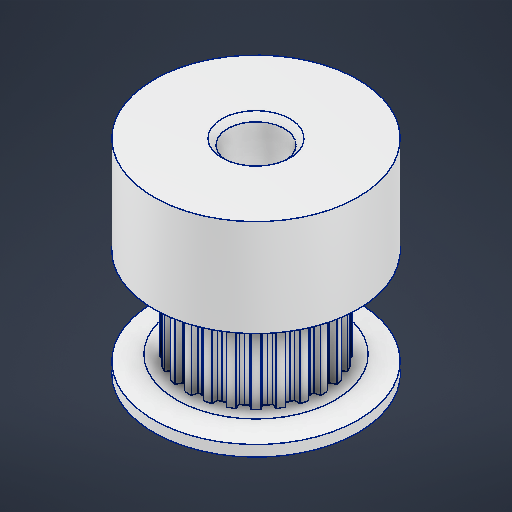
# Autodesk Inventor part: 24 Timing Belt Pulli
Saved by Autodesk Inventor 2026.2 (Build 302298010, 298A)
## iProperties
Created: 2026-04-26
Part Number: 24 Timing Belt Pulli
Material: 알루미늄 6061
Document SubType Name: Modeling
Designer: work
Density: 2.7 g/cm^3
Appearance: 알루미늄 - 평지
Author: work
Autodesk Inventor part; units mm, degrees
ref_plane "YZ Plane" through (0, 0, 0) normal (1, 0, 0) x (0, 1, 0)
ref_plane "XZ Plane" through (0, 0, 0) normal (0, 1, 0) x (-1, 0, 0)
ref_plane "XY Plane" through (0, 0, 0) normal (0, 0, 1) x (1, 0, 0)
sketch "스케치1" plane through (0, 0, 0) normal (0, 1, 0) x (-1, 0, 0)
  circle A0 centre (0, 0) radius 9
  circle A1 centre (0, 0) radius 2.5
  dimension "d0" = 18
  dimension "d1" = 5
  constraints: 2 centre point, 2 coincident
  measures "d0" diameter of A0
  measures "d1" diameter of A1
extrude "돌출1" add sketch "스케치1" along normal blind 18
ref_plane "작업 평면1" through (0, 1.5, 0) normal (0, -1, 0) x (1, 0, 0)
sketch "스케치2" plane through (0, 1.5, 0) normal (0, -1, 0) x (1, 0, 0)
  circle A0 centre (0, 0) radius 9 projected
  circle A1 centre (0, 0) radius 2.5 projected
  line L0 (0, 0) -> (0, -6) construction
  line L1 (0, -6) -> (0.3045, -6)
  line L2 (0.3045, -6) -> (0.3927, -5.5)
  line L3 (0.3927, -5.5) -> (0.7854, -5.5)
  line L4 (0, -6) -> (-0.3045, -6)
  line L5 (-0.3045, -6) -> (-0.3927, -5.5)
  line L6 (-0.3927, -5.5) -> (-0.7854, -5.5)
  line L7 (0, 0) -> (1.5529, -5.7956) construction
  line L8 (1.5529, -5.7956) -> (1.8471, -5.7167)
  line L9 (1.8471, -5.7167) -> (1.8028, -5.211)
  line L10 (1.8028, -5.211) -> (2.1821, -5.1093)
  line L11 (1.5529, -5.7956) -> (1.2588, -5.8744)
  line L12 (1.2588, -5.8744) -> (1.0442, -5.4142)
  line L13 (1.0442, -5.4142) -> (0.6649, -5.5159)
  line L14 (0, 0) -> (3, -5.1962) construction
  line L15 (3, -5.1962) -> (3.2637, -5.0439)
  line L16 (3.2637, -5.0439) -> (3.0901, -4.5668)
  line L17 (3.0901, -4.5668) -> (3.4302, -4.3704)
  line L18 (3, -5.1962) -> (2.7363, -5.3484)
  line L19 (2.7363, -5.3484) -> (2.4099, -4.9595)
  line L20 (2.4099, -4.9595) -> (2.0698, -5.1558)
  line L21 (0, 0) -> (4.2426, -4.2426) construction
  line L22 (4.2426, -4.2426) -> (4.458, -4.0273)
  line L23 (4.458, -4.0273) -> (4.1668, -3.6114)
  line L24 (4.1668, -3.6114) -> (4.4444, -3.3337)
  line L25 (4.2426, -4.2426) -> (4.0273, -4.458)
  line L26 (4.0273, -4.458) -> (3.6114, -4.1668)
  line L27 (3.6114, -4.1668) -> (3.3337, -4.4444)
  line L28 (0, 0) -> (5.1962, -3) construction
  line L29 (5.1962, -3) -> (5.3484, -2.7363)
  line L30 (5.3484, -2.7363) -> (4.9595, -2.4099)
  line L31 (4.9595, -2.4099) -> (5.1558, -2.0698)
  line L32 (5.1962, -3) -> (5.0439, -3.2637)
  line L33 (5.0439, -3.2637) -> (4.5668, -3.0901)
  line L34 (4.5668, -3.0901) -> (4.3704, -3.4302)
  line L35 (0, 0) -> (5.7956, -1.5529) construction
  line L36 (5.7956, -1.5529) -> (5.8744, -1.2588)
  line L37 (5.8744, -1.2588) -> (5.4142, -1.0442)
  line L38 (5.4142, -1.0442) -> (5.5159, -0.6649)
  line L39 (5.7956, -1.5529) -> (5.7167, -1.8471)
  line L40 (5.7167, -1.8471) -> (5.211, -1.8028)
  line L41 (5.211, -1.8028) -> (5.1093, -2.1821)
  line L42 (0, 0) -> (6, 0) construction
  line L43 (6, 0) -> (6, 0.3045)
  line L44 (6, 0.3045) -> (5.5, 0.3927)
  line L45 (5.5, 0.3927) -> (5.5, 0.7854)
  line L46 (6, 0) -> (6, -0.3045)
  line L47 (6, -0.3045) -> (5.5, -0.3927)
  line L48 (5.5, -0.3927) -> (5.5, -0.7854)
  line L49 (0, 0) -> (5.7956, 1.5529) construction
  line L50 (5.7956, 1.5529) -> (5.7167, 1.8471)
  line L51 (5.7167, 1.8471) -> (5.211, 1.8028)
  line L52 (5.211, 1.8028) -> (5.1093, 2.1821)
  line L53 (5.7956, 1.5529) -> (5.8744, 1.2588)
  line L54 (5.8744, 1.2588) -> (5.4142, 1.0442)
  line L55 (5.4142, 1.0442) -> (5.5159, 0.6649)
  line L56 (0, 0) -> (5.1962, 3) construction
  line L57 (5.1962, 3) -> (5.0439, 3.2637)
  line L58 (5.0439, 3.2637) -> (4.5668, 3.0901)
  line L59 (4.5668, 3.0901) -> (4.3704, 3.4302)
  line L60 (5.1962, 3) -> (5.3484, 2.7363)
  line L61 (5.3484, 2.7363) -> (4.9595, 2.4099)
  line L62 (4.9595, 2.4099) -> (5.1558, 2.0698)
  line L63 (0, 0) -> (4.2426, 4.2426) construction
  line L64 (4.2426, 4.2426) -> (4.0273, 4.458)
  line L65 (4.0273, 4.458) -> (3.6114, 4.1668)
  line L66 (3.6114, 4.1668) -> (3.3337, 4.4444)
  line L67 (4.2426, 4.2426) -> (4.458, 4.0273)
  line L68 (4.458, 4.0273) -> (4.1668, 3.6114)
  line L69 (4.1668, 3.6114) -> (4.4444, 3.3337)
  line L70 (0, 0) -> (3, 5.1962) construction
  line L71 (3, 5.1962) -> (2.7363, 5.3484)
  line L72 (2.7363, 5.3484) -> (2.4099, 4.9595)
  line L73 (2.4099, 4.9595) -> (2.0698, 5.1558)
  line L74 (3, 5.1962) -> (3.2637, 5.0439)
  line L75 (3.2637, 5.0439) -> (3.0901, 4.5668)
  line L76 (3.0901, 4.5668) -> (3.4302, 4.3704)
  line L77 (0, 0) -> (1.5529, 5.7956) construction
  line L78 (1.5529, 5.7956) -> (1.2588, 5.8744)
  line L79 (1.2588, 5.8744) -> (1.0442, 5.4142)
  line L80 (1.0442, 5.4142) -> (0.6649, 5.5159)
  line L81 (1.5529, 5.7956) -> (1.8471, 5.7167)
  line L82 (1.8471, 5.7167) -> (1.8028, 5.211)
  line L83 (1.8028, 5.211) -> (2.1821, 5.1093)
  line L84 (0, 0) -> (0, 6) construction
  line L85 (0, 6) -> (-0.3045, 6)
  line L86 (-0.3045, 6) -> (-0.3927, 5.5)
  line L87 (-0.3927, 5.5) -> (-0.7854, 5.5)
  line L88 (0, 6) -> (0.3045, 6)
  line L89 (0.3045, 6) -> (0.3927, 5.5)
  line L90 (0.3927, 5.5) -> (0.7854, 5.5)
  line L91 (0, 0) -> (-1.5529, 5.7956) construction
  line L92 (-1.5529, 5.7956) -> (-1.8471, 5.7167)
  line L93 (-1.8471, 5.7167) -> (-1.8028, 5.211)
  line L94 (-1.8028, 5.211) -> (-2.1821, 5.1093)
  line L95 (-1.5529, 5.7956) -> (-1.2588, 5.8744)
  line L96 (-1.2588, 5.8744) -> (-1.0442, 5.4142)
  line L97 (-1.0442, 5.4142) -> (-0.6649, 5.5159)
  line L98 (0, 0) -> (-3, 5.1962) construction
  line L99 (-3, 5.1962) -> (-3.2637, 5.0439)
  line L100 (-3.2637, 5.0439) -> (-3.0901, 4.5668)
  line L101 (-3.0901, 4.5668) -> (-3.4302, 4.3704)
  line L102 (-3, 5.1962) -> (-2.7363, 5.3484)
  line L103 (-2.7363, 5.3484) -> (-2.4099, 4.9595)
  line L104 (-2.4099, 4.9595) -> (-2.0698, 5.1558)
  line L105 (0, 0) -> (-4.2426, 4.2426) construction
  line L106 (-4.2426, 4.2426) -> (-4.458, 4.0273)
  line L107 (-4.458, 4.0273) -> (-4.1668, 3.6114)
  line L108 (-4.1668, 3.6114) -> (-4.4444, 3.3337)
  line L109 (-4.2426, 4.2426) -> (-4.0273, 4.458)
  line L110 (-4.0273, 4.458) -> (-3.6114, 4.1668)
  line L111 (-3.6114, 4.1668) -> (-3.3337, 4.4444)
  line L112 (0, 0) -> (-5.1962, 3) construction
  line L113 (-5.1962, 3) -> (-5.3484, 2.7363)
  line L114 (-5.3484, 2.7363) -> (-4.9595, 2.4099)
  line L115 (-4.9595, 2.4099) -> (-5.1558, 2.0698)
  line L116 (-5.1962, 3) -> (-5.0439, 3.2637)
  line L117 (-5.0439, 3.2637) -> (-4.5668, 3.0901)
  line L118 (-4.5668, 3.0901) -> (-4.3704, 3.4302)
  line L119 (0, 0) -> (-5.7956, 1.5529) construction
  line L120 (-5.7956, 1.5529) -> (-5.8744, 1.2588)
  line L121 (-5.8744, 1.2588) -> (-5.4142, 1.0442)
  line L122 (-5.4142, 1.0442) -> (-5.5159, 0.6649)
  line L123 (-5.7956, 1.5529) -> (-5.7167, 1.8471)
  line L124 (-5.7167, 1.8471) -> (-5.211, 1.8028)
  line L125 (-5.211, 1.8028) -> (-5.1093, 2.1821)
  line L126 (0, 0) -> (-6, 0) construction
  line L127 (-6, 0) -> (-6, -0.3045)
  line L128 (-6, -0.3045) -> (-5.5, -0.3927)
  line L129 (-5.5, -0.3927) -> (-5.5, -0.7854)
  line L130 (-6, 0) -> (-6, 0.3045)
  line L131 (-6, 0.3045) -> (-5.5, 0.3927)
  line L132 (-5.5, 0.3927) -> (-5.5, 0.7854)
  line L133 (0, 0) -> (-5.7956, -1.5529) construction
  line L134 (-5.7956, -1.5529) -> (-5.7167, -1.8471)
  line L135 (-5.7167, -1.8471) -> (-5.211, -1.8028)
  line L136 (-5.211, -1.8028) -> (-5.1093, -2.1821)
  line L137 (-5.7956, -1.5529) -> (-5.8744, -1.2588)
  line L138 (-5.8744, -1.2588) -> (-5.4142, -1.0442)
  line L139 (-5.4142, -1.0442) -> (-5.5159, -0.6649)
  line L140 (0, 0) -> (-5.1962, -3) construction
  line L141 (-5.1962, -3) -> (-5.0439, -3.2637)
  line L142 (-5.0439, -3.2637) -> (-4.5668, -3.0901)
  line L143 (-4.5668, -3.0901) -> (-4.3704, -3.4302)
  line L144 (-5.1962, -3) -> (-5.3484, -2.7363)
  line L145 (-5.3484, -2.7363) -> (-4.9595, -2.4099)
  line L146 (-4.9595, -2.4099) -> (-5.1558, -2.0698)
  line L147 (0, 0) -> (-4.2426, -4.2426) construction
  line L148 (-4.2426, -4.2426) -> (-4.0273, -4.458)
  line L149 (-4.0273, -4.458) -> (-3.6114, -4.1668)
  line L150 (-3.6114, -4.1668) -> (-3.3337, -4.4444)
  line L151 (-4.2426, -4.2426) -> (-4.458, -4.0273)
  line L152 (-4.458, -4.0273) -> (-4.1668, -3.6114)
  line L153 (-4.1668, -3.6114) -> (-4.4444, -3.3337)
  line L154 (0, 0) -> (-3, -5.1962) construction
  line L155 (-3, -5.1962) -> (-2.7363, -5.3484)
  line L156 (-2.7363, -5.3484) -> (-2.4099, -4.9595)
  line L157 (-2.4099, -4.9595) -> (-2.0698, -5.1558)
  line L158 (-3, -5.1962) -> (-3.2637, -5.0439)
  line L159 (-3.2637, -5.0439) -> (-3.0901, -4.5668)
  line L160 (-3.0901, -4.5668) -> (-3.4302, -4.3704)
  line L161 (0, 0) -> (-1.5529, -5.7956) construction
  line L162 (-1.5529, -5.7956) -> (-1.2588, -5.8744)
  line L163 (-1.2588, -5.8744) -> (-1.0442, -5.4142)
  line L164 (-1.0442, -5.4142) -> (-0.6649, -5.5159)
  line L165 (-1.5529, -5.7956) -> (-1.8471, -5.7167)
  line L166 (-1.8471, -5.7167) -> (-1.8028, -5.211)
  line L167 (-1.8028, -5.211) -> (-2.1821, -5.1093)
  point P0 (-0.7241, -5.5)
  point P1 (-2.1229, -5.1252)
  point P2 (-3.3771, -4.4011)
  point P3 (-4.4011, -3.3771)
  point P4 (-5.1252, -2.1229)
  point P5 (-5.5, -0.7241)
  point P6 (-5.5, 0.7241)
  point P7 (-5.1252, 2.1229)
  point P8 (-4.4011, 3.3771)
  point P9 (-3.3771, 4.4011)
  point P10 (-2.1229, 5.1252)
  point P11 (-0.7241, 5.5)
  point P12 (0.7241, 5.5)
  point P13 (2.1229, 5.1252)
  point P14 (3.3771, 4.4011)
  point P15 (4.4011, 3.3771)
  point P16 (5.1252, 2.1229)
  point P17 (5.5, 0.7241)
  point P18 (5.5, -0.7241)
  point P19 (5.1252, -2.1229)
  point P20 (4.4011, -3.3771)
  point P21 (3.3771, -4.4011)
  point P22 (2.1229, -5.1252)
  point P23 (0.7241, -5.5)
  dimension "d5" = 1.5708
  dimension "d6" = 6
  dimension "d7" = 100
  dimension "d8" = 0.3927
  dimension "d9" = 0.5
  dimension "d12" = 360
  constraints: 336 end point, 3 symmetric about line, 2 coincident, 1 parallel, 1 perpendicular, 1 vertical, 359 other
  measures "d5" distance of L3.end L6.end
  measures "d6" distance of L0.start L0.end
  measures "d7" angle of L2 L1
  measures "d8" distance of L2.end L3.end
  measures "d9" vertical distance of L2.end L1.end
extrude "돌출2" cut sketch "스케치2" against normal blind 7.4 contours A0
sketch "스케치3" plane through (0, 0, 0) normal (0, 0, 1) x (1, 0, 0)
  line L0 (-2.5, 18) -> (2.5, 18) projected
  line L1 (0, 18) -> (0, 14) construction
  circle A0 centre (0, 12.75) radius 1.25
  line L2 (0, 14) -> (0, 12.75) construction
  point P0 (0, 0)
  dimension "d17" = 2.5
  dimension "d16" = 4
  constraints: 4 end point, 2 vertical, 1 midpoint, 1 vertical alignment, 2 other
  measures "d16" distance of L1.start L1.end
extrude "돌출3" cut sketch "스케치3" against normal through all
chamfer "모따기1" distance 1.5 angle 45 1 edges at (-1.25, 12.753, -8.9128)
thread "스레드1" size "M2.5x0.45" class "6H" standard "ISO Metric profile" full length
pattern_circular "원형 패턴1" count 4 over 360 about axis through (0, -10, 0) along (0, 1, 0) of "돌출3", "모따기1" skipped copies 3 4
chamfer "모따기4" distance 2 angle 15 1 edges at (9, 8.9, 0) measured on face at (8.5, 8.9, 0)
chamfer "모따기3" distance 2 angle 15 1 edges at (9, 1.5, 0) measured on face at (8.5, 1.5, 0)
chamfer "모따기2" distance 0.5 angle 45 2 edges at (2.5, 18, 0) (2.5, 0, 0)
equation "\"d8\" = 0.25 * d5"
